Autodesk Fusion 360 part; units mm, degrees
(part 2 of 2)
sketch "草图103" plane through (0, 0, 0) normal (0, 0, 1) x (1, 0, 0) in component "scene_go"
  line L0 (9.75, 106.25) -> (32.75, 106.25) construction
  arc A0 (30.75, 106.25) -> (11.75, 106.25) centre (21.25, 87.3194) ccw
  arc A1 (11.75, 106.25) -> (30.75, 106.25) centre (21.25, 125.1806) ccw
revolve "旋转103" add sketch "草图103" angle 360 about axis through (9.75, 106.25, 0) along (1, 0, 0) separate body makes body 104 in component "scene_go"
sketch "草图104" plane through (0, 0, 0) normal (0, 0, 1) x (1, 0, 0) in component "scene_go"
  line L0 (9.75, 127.5) -> (32.75, 127.5) construction
  arc A0 (30.75, 127.5) -> (11.75, 127.5) centre (21.25, 108.5694) ccw
  arc A1 (11.75, 127.5) -> (30.75, 127.5) centre (21.25, 146.4306) ccw
revolve "旋转104" add sketch "草图104" angle 360 about axis through (9.75, 127.5, 0) along (1, 0, 0) separate body makes body 105 in component "scene_go"
sketch "草图105" plane through (0, 0, 0) normal (0, 0, 1) x (1, 0, 0) in component "scene_go"
  line L0 (31, -127.5) -> (54, -127.5) construction
  arc A0 (52, -127.5) -> (33, -127.5) centre (42.5, -146.4306) ccw
  arc A1 (33, -127.5) -> (52, -127.5) centre (42.5, -108.5694) ccw
revolve "旋转105" add sketch "草图105" angle 360 about axis through (31, -127.5, 0) along (1, 0, 0) separate body makes body 106 in component "scene_go"
sketch "草图106" plane through (0, 0, 0) normal (0, 0, 1) x (1, 0, 0) in component "scene_go"
  line L0 (31, -106.25) -> (54, -106.25) construction
  arc A0 (52, -106.25) -> (33, -106.25) centre (42.5, -125.1806) ccw
  arc A1 (33, -106.25) -> (52, -106.25) centre (42.5, -87.3194) ccw
revolve "旋转106" add sketch "草图106" angle 360 about axis through (31, -106.25, 0) along (1, 0, 0) separate body makes body 107 in component "scene_go"
sketch "草图107" plane through (0, 0, 0) normal (0, 0, 1) x (1, 0, 0) in component "scene_go"
  line L0 (31, -85) -> (54, -85) construction
  arc A0 (52, -85) -> (33, -85) centre (42.5, -103.9306) ccw
  arc A1 (33, -85) -> (52, -85) centre (42.5, -66.0694) ccw
revolve "旋转107" add sketch "草图107" angle 360 about axis through (31, -85, 0) along (1, 0, 0) separate body makes body 108 in component "scene_go"
sketch "草图108" plane through (0, 0, 0) normal (0, 0, 1) x (1, 0, 0) in component "scene_go"
  line L0 (31, -63.75) -> (54, -63.75) construction
  arc A0 (52, -63.75) -> (33, -63.75) centre (42.5, -82.6806) ccw
  arc A1 (33, -63.75) -> (52, -63.75) centre (42.5, -44.8194) ccw
revolve "旋转108" add sketch "草图108" angle 360 about axis through (31, -63.75, 0) along (1, 0, 0) separate body makes body 109 in component "scene_go"
sketch "草图109" plane through (0, 0, 0) normal (0, 0, 1) x (1, 0, 0) in component "scene_go"
  line L0 (31, -42.5) -> (54, -42.5) construction
  arc A0 (52, -42.5) -> (33, -42.5) centre (42.5, -61.4306) ccw
  arc A1 (33, -42.5) -> (52, -42.5) centre (42.5, -23.5694) ccw
revolve "旋转109" add sketch "草图109" angle 360 about axis through (31, -42.5, 0) along (1, 0, 0) separate body makes body 110 in component "scene_go"
sketch "草图110" plane through (0, 0, 0) normal (0, 0, 1) x (1, 0, 0) in component "scene_go"
  line L0 (31, -21.25) -> (54, -21.25) construction
  arc A0 (52, -21.25) -> (33, -21.25) centre (42.5, -40.1806) ccw
  arc A1 (33, -21.25) -> (52, -21.25) centre (42.5, -2.3194) ccw
revolve "旋转110" add sketch "草图110" angle 360 about axis through (31, -21.25, 0) along (1, 0, 0) separate body makes body 111 in component "scene_go"
sketch "草图111" plane through (0, 0, 0) normal (0, 0, 1) x (1, 0, 0) in component "scene_go"
  line L0 (31, 0) -> (54, 0) construction
  arc A0 (52, 0) -> (33, 0) centre (42.5, -18.9306) ccw
  arc A1 (33, 0) -> (52, 0) centre (42.5, 18.9306) ccw
revolve "旋转111" add sketch "草图111" angle 360 about axis through (31, 0, 0) along (1, 0, 0) separate body makes body 112 in component "scene_go"
sketch "草图112" plane through (0, 0, 0) normal (0, 0, 1) x (1, 0, 0) in component "scene_go"
  line L0 (31, 21.25) -> (54, 21.25) construction
  arc A0 (52, 21.25) -> (33, 21.25) centre (42.5, 2.3194) ccw
  arc A1 (33, 21.25) -> (52, 21.25) centre (42.5, 40.1806) ccw
revolve "旋转112" add sketch "草图112" angle 360 about axis through (31, 21.25, 0) along (1, 0, 0) separate body makes body 113 in component "scene_go"
sketch "草图113" plane through (0, 0, 0) normal (0, 0, 1) x (1, 0, 0) in component "scene_go"
  line L0 (31, 42.5) -> (54, 42.5) construction
  arc A0 (52, 42.5) -> (33, 42.5) centre (42.5, 23.5694) ccw
  arc A1 (33, 42.5) -> (52, 42.5) centre (42.5, 61.4306) ccw
revolve "旋转113" add sketch "草图113" angle 360 about axis through (31, 42.5, 0) along (1, 0, 0) separate body makes body 114 in component "scene_go"
sketch "草图114" plane through (0, 0, 0) normal (0, 0, 1) x (1, 0, 0) in component "scene_go"
  line L0 (31, 63.75) -> (54, 63.75) construction
  arc A0 (52, 63.75) -> (33, 63.75) centre (42.5, 44.8194) ccw
  arc A1 (33, 63.75) -> (52, 63.75) centre (42.5, 82.6806) ccw
revolve "旋转114" add sketch "草图114" angle 360 about axis through (31, 63.75, 0) along (1, 0, 0) separate body makes body 115 in component "scene_go"
sketch "草图115" plane through (0, 0, 0) normal (0, 0, 1) x (1, 0, 0) in component "scene_go"
  line L0 (31, 85) -> (54, 85) construction
  arc A0 (52, 85) -> (33, 85) centre (42.5, 66.0694) ccw
  arc A1 (33, 85) -> (52, 85) centre (42.5, 103.9306) ccw
revolve "旋转115" add sketch "草图115" angle 360 about axis through (31, 85, 0) along (1, 0, 0) separate body makes body 116 in component "scene_go"
sketch "草图116" plane through (0, 0, 0) normal (0, 0, 1) x (1, 0, 0) in component "scene_go"
  line L0 (31, 106.25) -> (54, 106.25) construction
  arc A0 (52, 106.25) -> (33, 106.25) centre (42.5, 87.3194) ccw
  arc A1 (33, 106.25) -> (52, 106.25) centre (42.5, 125.1806) ccw
revolve "旋转116" add sketch "草图116" angle 360 about axis through (31, 106.25, 0) along (1, 0, 0) separate body makes body 117 in component "scene_go"
sketch "草图117" plane through (0, 0, 0) normal (0, 0, 1) x (1, 0, 0) in component "scene_go"
  line L0 (31, 127.5) -> (54, 127.5) construction
  arc A0 (52, 127.5) -> (33, 127.5) centre (42.5, 108.5694) ccw
  arc A1 (33, 127.5) -> (52, 127.5) centre (42.5, 146.4306) ccw
revolve "旋转117" add sketch "草图117" angle 360 about axis through (31, 127.5, 0) along (1, 0, 0) separate body makes body 118 in component "scene_go"
sketch "草图118" plane through (0, 0, 0) normal (0, 0, 1) x (1, 0, 0) in component "scene_go"
  line L0 (52.25, -127.5) -> (75.25, -127.5) construction
  arc A0 (73.25, -127.5) -> (54.25, -127.5) centre (63.75, -146.4306) ccw
  arc A1 (54.25, -127.5) -> (73.25, -127.5) centre (63.75, -108.5694) ccw
revolve "旋转118" add sketch "草图118" angle 360 about axis through (52.25, -127.5, 0) along (1, 0, 0) separate body makes body 119 in component "scene_go"
sketch "草图119" plane through (0, 0, 0) normal (0, 0, 1) x (1, 0, 0) in component "scene_go"
  line L0 (52.25, -106.25) -> (75.25, -106.25) construction
  arc A0 (73.25, -106.25) -> (54.25, -106.25) centre (63.75, -125.1806) ccw
  arc A1 (54.25, -106.25) -> (73.25, -106.25) centre (63.75, -87.3194) ccw
revolve "旋转119" add sketch "草图119" angle 360 about axis through (52.25, -106.25, 0) along (1, 0, 0) separate body makes body 120 in component "scene_go"
sketch "草图120" plane through (0, 0, 0) normal (0, 0, 1) x (1, 0, 0) in component "scene_go"
  line L0 (52.25, -85) -> (75.25, -85) construction
  arc A0 (73.25, -85) -> (54.25, -85) centre (63.75, -103.9306) ccw
  arc A1 (54.25, -85) -> (73.25, -85) centre (63.75, -66.0694) ccw
revolve "旋转120" add sketch "草图120" angle 360 about axis through (52.25, -85, 0) along (1, 0, 0) separate body makes body 121 in component "scene_go"
sketch "草图121" plane through (0, 0, 0) normal (0, 0, 1) x (1, 0, 0) in component "scene_go"
  line L0 (52.25, -63.75) -> (75.25, -63.75) construction
  arc A0 (73.25, -63.75) -> (54.25, -63.75) centre (63.75, -82.6806) ccw
  arc A1 (54.25, -63.75) -> (73.25, -63.75) centre (63.75, -44.8194) ccw
revolve "旋转121" add sketch "草图121" angle 360 about axis through (52.25, -63.75, 0) along (1, 0, 0) separate body makes body 122 in component "scene_go"
sketch "草图122" plane through (0, 0, 0) normal (0, 0, 1) x (1, 0, 0) in component "scene_go"
  line L0 (52.25, -42.5) -> (75.25, -42.5) construction
  arc A0 (73.25, -42.5) -> (54.25, -42.5) centre (63.75, -61.4306) ccw
  arc A1 (54.25, -42.5) -> (73.25, -42.5) centre (63.75, -23.5694) ccw
revolve "旋转122" add sketch "草图122" angle 360 about axis through (52.25, -42.5, 0) along (1, 0, 0) separate body makes body 123 in component "scene_go"
sketch "草图123" plane through (0, 0, 0) normal (0, 0, 1) x (1, 0, 0) in component "scene_go"
  line L0 (52.25, -21.25) -> (75.25, -21.25) construction
  arc A0 (73.25, -21.25) -> (54.25, -21.25) centre (63.75, -40.1806) ccw
  arc A1 (54.25, -21.25) -> (73.25, -21.25) centre (63.75, -2.3194) ccw
revolve "旋转123" add sketch "草图123" angle 360 about axis through (52.25, -21.25, 0) along (1, 0, 0) separate body makes body 124 in component "scene_go"
sketch "草图124" plane through (0, 0, 0) normal (0, 0, 1) x (1, 0, 0) in component "scene_go"
  line L0 (52.25, 0) -> (75.25, 0) construction
  arc A0 (73.25, 0) -> (54.25, 0) centre (63.75, -18.9306) ccw
  arc A1 (54.25, 0) -> (73.25, 0) centre (63.75, 18.9306) ccw
revolve "旋转124" add sketch "草图124" angle 360 about axis through (52.25, 0, 0) along (1, 0, 0) separate body makes body 125 in component "scene_go"
sketch "草图125" plane through (0, 0, 0) normal (0, 0, 1) x (1, 0, 0) in component "scene_go"
  line L0 (52.25, 21.25) -> (75.25, 21.25) construction
  arc A0 (73.25, 21.25) -> (54.25, 21.25) centre (63.75, 2.3194) ccw
  arc A1 (54.25, 21.25) -> (73.25, 21.25) centre (63.75, 40.1806) ccw
revolve "旋转125" add sketch "草图125" angle 360 about axis through (52.25, 21.25, 0) along (1, 0, 0) separate body makes body 126 in component "scene_go"
sketch "草图126" plane through (0, 0, 0) normal (0, 0, 1) x (1, 0, 0) in component "scene_go"
  line L0 (52.25, 42.5) -> (75.25, 42.5) construction
  arc A0 (73.25, 42.5) -> (54.25, 42.5) centre (63.75, 23.5694) ccw
  arc A1 (54.25, 42.5) -> (73.25, 42.5) centre (63.75, 61.4306) ccw
revolve "旋转126" add sketch "草图126" angle 360 about axis through (52.25, 42.5, 0) along (1, 0, 0) separate body makes body 127 in component "scene_go"
sketch "草图127" plane through (0, 0, 0) normal (0, 0, 1) x (1, 0, 0) in component "scene_go"
  line L0 (52.25, 63.75) -> (75.25, 63.75) construction
  arc A0 (73.25, 63.75) -> (54.25, 63.75) centre (63.75, 44.8194) ccw
  arc A1 (54.25, 63.75) -> (73.25, 63.75) centre (63.75, 82.6806) ccw
revolve "旋转127" add sketch "草图127" angle 360 about axis through (52.25, 63.75, 0) along (1, 0, 0) separate body makes body 128 in component "scene_go"
sketch "草图128" plane through (0, 0, 0) normal (0, 0, 1) x (1, 0, 0) in component "scene_go"
  line L0 (52.25, 85) -> (75.25, 85) construction
  arc A0 (73.25, 85) -> (54.25, 85) centre (63.75, 66.0694) ccw
  arc A1 (54.25, 85) -> (73.25, 85) centre (63.75, 103.9306) ccw
revolve "旋转128" add sketch "草图128" angle 360 about axis through (52.25, 85, 0) along (1, 0, 0) separate body makes body 129 in component "scene_go"
sketch "草图129" plane through (0, 0, 0) normal (0, 0, 1) x (1, 0, 0) in component "scene_go"
  line L0 (52.25, 106.25) -> (75.25, 106.25) construction
  arc A0 (73.25, 106.25) -> (54.25, 106.25) centre (63.75, 87.3194) ccw
  arc A1 (54.25, 106.25) -> (73.25, 106.25) centre (63.75, 125.1806) ccw
revolve "旋转129" add sketch "草图129" angle 360 about axis through (52.25, 106.25, 0) along (1, 0, 0) separate body makes body 130 in component "scene_go"
sketch "草图130" plane through (0, 0, 0) normal (0, 0, 1) x (1, 0, 0) in component "scene_go"
  line L0 (52.25, 127.5) -> (75.25, 127.5) construction
  arc A0 (73.25, 127.5) -> (54.25, 127.5) centre (63.75, 108.5694) ccw
  arc A1 (54.25, 127.5) -> (73.25, 127.5) centre (63.75, 146.4306) ccw
revolve "旋转130" add sketch "草图130" angle 360 about axis through (52.25, 127.5, 0) along (1, 0, 0) separate body makes body 131 in component "scene_go"
sketch "草图131" plane through (0, 0, 0) normal (0, 0, 1) x (1, 0, 0) in component "scene_go"
  line L0 (73.5, -127.5) -> (96.5, -127.5) construction
  arc A0 (94.5, -127.5) -> (75.5, -127.5) centre (85, -146.4306) ccw
  arc A1 (75.5, -127.5) -> (94.5, -127.5) centre (85, -108.5694) ccw
revolve "旋转131" add sketch "草图131" angle 360 about axis through (73.5, -127.5, 0) along (1, 0, 0) separate body makes body 132 in component "scene_go"
sketch "草图132" plane through (0, 0, 0) normal (0, 0, 1) x (1, 0, 0) in component "scene_go"
  line L0 (73.5, -106.25) -> (96.5, -106.25) construction
  arc A0 (94.5, -106.25) -> (75.5, -106.25) centre (85, -125.1806) ccw
  arc A1 (75.5, -106.25) -> (94.5, -106.25) centre (85, -87.3194) ccw
revolve "旋转132" add sketch "草图132" angle 360 about axis through (73.5, -106.25, 0) along (1, 0, 0) separate body makes body 133 in component "scene_go"
sketch "草图133" plane through (0, 0, 0) normal (0, 0, 1) x (1, 0, 0) in component "scene_go"
  line L0 (73.5, -85) -> (96.5, -85) construction
  arc A0 (94.5, -85) -> (75.5, -85) centre (85, -103.9306) ccw
  arc A1 (75.5, -85) -> (94.5, -85) centre (85, -66.0694) ccw
revolve "旋转133" add sketch "草图133" angle 360 about axis through (73.5, -85, 0) along (1, 0, 0) separate body makes body 134 in component "scene_go"
sketch "草图134" plane through (0, 0, 0) normal (0, 0, 1) x (1, 0, 0) in component "scene_go"
  line L0 (73.5, -63.75) -> (96.5, -63.75) construction
  arc A0 (94.5, -63.75) -> (75.5, -63.75) centre (85, -82.6806) ccw
  arc A1 (75.5, -63.75) -> (94.5, -63.75) centre (85, -44.8194) ccw
revolve "旋转134" add sketch "草图134" angle 360 about axis through (73.5, -63.75, 0) along (1, 0, 0) separate body makes body 135 in component "scene_go"
sketch "草图135" plane through (0, 0, 0) normal (0, 0, 1) x (1, 0, 0) in component "scene_go"
  line L0 (73.5, -42.5) -> (96.5, -42.5) construction
  arc A0 (94.5, -42.5) -> (75.5, -42.5) centre (85, -61.4306) ccw
  arc A1 (75.5, -42.5) -> (94.5, -42.5) centre (85, -23.5694) ccw
revolve "旋转135" add sketch "草图135" angle 360 about axis through (73.5, -42.5, 0) along (1, 0, 0) separate body makes body 136 in component "scene_go"
sketch "草图136" plane through (0, 0, 0) normal (0, 0, 1) x (1, 0, 0) in component "scene_go"
  line L0 (73.5, -21.25) -> (96.5, -21.25) construction
  arc A0 (94.5, -21.25) -> (75.5, -21.25) centre (85, -40.1806) ccw
  arc A1 (75.5, -21.25) -> (94.5, -21.25) centre (85, -2.3194) ccw
revolve "旋转136" add sketch "草图136" angle 360 about axis through (73.5, -21.25, 0) along (1, 0, 0) separate body makes body 137 in component "scene_go"
sketch "草图137" plane through (0, 0, 0) normal (0, 0, 1) x (1, 0, 0) in component "scene_go"
  line L0 (73.5, 0) -> (96.5, 0) construction
  arc A0 (94.5, 0) -> (75.5, 0) centre (85, -18.9306) ccw
  arc A1 (75.5, 0) -> (94.5, 0) centre (85, 18.9306) ccw
revolve "旋转137" add sketch "草图137" angle 360 about axis through (73.5, 0, 0) along (1, 0, 0) separate body makes body 138 in component "scene_go"
sketch "草图138" plane through (0, 0, 0) normal (0, 0, 1) x (1, 0, 0) in component "scene_go"
  line L0 (73.5, 21.25) -> (96.5, 21.25) construction
  arc A0 (94.5, 21.25) -> (75.5, 21.25) centre (85, 2.3194) ccw
  arc A1 (75.5, 21.25) -> (94.5, 21.25) centre (85, 40.1806) ccw
revolve "旋转138" add sketch "草图138" angle 360 about axis through (73.5, 21.25, 0) along (1, 0, 0) separate body makes body 139 in component "scene_go"
sketch "草图139" plane through (0, 0, 0) normal (0, 0, 1) x (1, 0, 0) in component "scene_go"
  line L0 (73.5, 42.5) -> (96.5, 42.5) construction
  arc A0 (94.5, 42.5) -> (75.5, 42.5) centre (85, 23.5694) ccw
  arc A1 (75.5, 42.5) -> (94.5, 42.5) centre (85, 61.4306) ccw
revolve "旋转139" add sketch "草图139" angle 360 about axis through (73.5, 42.5, 0) along (1, 0, 0) separate body makes body 140 in component "scene_go"
sketch "草图140" plane through (0, 0, 0) normal (0, 0, 1) x (1, 0, 0) in component "scene_go"
  line L0 (73.5, 63.75) -> (96.5, 63.75) construction
  arc A0 (94.5, 63.75) -> (75.5, 63.75) centre (85, 44.8194) ccw
  arc A1 (75.5, 63.75) -> (94.5, 63.75) centre (85, 82.6806) ccw
revolve "旋转140" add sketch "草图140" angle 360 about axis through (73.5, 63.75, 0) along (1, 0, 0) separate body makes body 141 in component "scene_go"
sketch "草图141" plane through (0, 0, 0) normal (0, 0, 1) x (1, 0, 0) in component "scene_go"
  line L0 (73.5, 85) -> (96.5, 85) construction
  arc A0 (94.5, 85) -> (75.5, 85) centre (85, 66.0694) ccw
  arc A1 (75.5, 85) -> (94.5, 85) centre (85, 103.9306) ccw
revolve "旋转141" add sketch "草图141" angle 360 about axis through (73.5, 85, 0) along (1, 0, 0) separate body makes body 142 in component "scene_go"
sketch "草图142" plane through (0, 0, 0) normal (0, 0, 1) x (1, 0, 0) in component "scene_go"
  line L0 (73.5, 106.25) -> (96.5, 106.25) construction
  arc A0 (94.5, 106.25) -> (75.5, 106.25) centre (85, 87.3194) ccw
  arc A1 (75.5, 106.25) -> (94.5, 106.25) centre (85, 125.1806) ccw
revolve "旋转142" add sketch "草图142" angle 360 about axis through (73.5, 106.25, 0) along (1, 0, 0) separate body makes body 143 in component "scene_go"
sketch "草图143" plane through (0, 0, 0) normal (0, 0, 1) x (1, 0, 0) in component "scene_go"
  line L0 (73.5, 127.5) -> (96.5, 127.5) construction
  arc A0 (94.5, 127.5) -> (75.5, 127.5) centre (85, 108.5694) ccw
  arc A1 (75.5, 127.5) -> (94.5, 127.5) centre (85, 146.4306) ccw
revolve "旋转143" add sketch "草图143" angle 360 about axis through (73.5, 127.5, 0) along (1, 0, 0) separate body makes body 144 in component "scene_go"
sketch "草图144" plane through (0, 0, 0) normal (0, 0, 1) x (1, 0, 0) in component "scene_go"
  line L0 (94.75, -127.5) -> (117.75, -127.5) construction
  arc A0 (115.75, -127.5) -> (96.75, -127.5) centre (106.25, -146.4306) ccw
  arc A1 (96.75, -127.5) -> (115.75, -127.5) centre (106.25, -108.5694) ccw
revolve "旋转144" add sketch "草图144" angle 360 about axis through (94.75, -127.5, 0) along (1, 0, 0) separate body makes body 145 in component "scene_go"
sketch "草图145" plane through (0, 0, 0) normal (0, 0, 1) x (1, 0, 0) in component "scene_go"
  line L0 (94.75, -106.25) -> (117.75, -106.25) construction
  arc A0 (115.75, -106.25) -> (96.75, -106.25) centre (106.25, -125.1806) ccw
  arc A1 (96.75, -106.25) -> (115.75, -106.25) centre (106.25, -87.3194) ccw
revolve "旋转145" add sketch "草图145" angle 360 about axis through (94.75, -106.25, 0) along (1, 0, 0) separate body makes body 146 in component "scene_go"
sketch "草图146" plane through (0, 0, 0) normal (0, 0, 1) x (1, 0, 0) in component "scene_go"
  line L0 (94.75, -85) -> (117.75, -85) construction
  arc A0 (115.75, -85) -> (96.75, -85) centre (106.25, -103.9306) ccw
  arc A1 (96.75, -85) -> (115.75, -85) centre (106.25, -66.0694) ccw
revolve "旋转146" add sketch "草图146" angle 360 about axis through (94.75, -85, 0) along (1, 0, 0) separate body makes body 147 in component "scene_go"
sketch "草图147" plane through (0, 0, 0) normal (0, 0, 1) x (1, 0, 0) in component "scene_go"
  line L0 (94.75, -63.75) -> (117.75, -63.75) construction
  arc A0 (115.75, -63.75) -> (96.75, -63.75) centre (106.25, -82.6806) ccw
  arc A1 (96.75, -63.75) -> (115.75, -63.75) centre (106.25, -44.8194) ccw
revolve "旋转147" add sketch "草图147" angle 360 about axis through (94.75, -63.75, 0) along (1, 0, 0) separate body makes body 148 in component "scene_go"
sketch "草图148" plane through (0, 0, 0) normal (0, 0, 1) x (1, 0, 0) in component "scene_go"
  line L0 (94.75, -42.5) -> (117.75, -42.5) construction
  arc A0 (115.75, -42.5) -> (96.75, -42.5) centre (106.25, -61.4306) ccw
  arc A1 (96.75, -42.5) -> (115.75, -42.5) centre (106.25, -23.5694) ccw
revolve "旋转148" add sketch "草图148" angle 360 about axis through (94.75, -42.5, 0) along (1, 0, 0) separate body makes body 149 in component "scene_go"
sketch "草图149" plane through (0, 0, 0) normal (0, 0, 1) x (1, 0, 0) in component "scene_go"
  line L0 (94.75, -21.25) -> (117.75, -21.25) construction
  arc A0 (115.75, -21.25) -> (96.75, -21.25) centre (106.25, -40.1806) ccw
  arc A1 (96.75, -21.25) -> (115.75, -21.25) centre (106.25, -2.3194) ccw
revolve "旋转149" add sketch "草图149" angle 360 about axis through (94.75, -21.25, 0) along (1, 0, 0) separate body makes body 150 in component "scene_go"
sketch "草图150" plane through (0, 0, 0) normal (0, 0, 1) x (1, 0, 0) in component "scene_go"
  line L0 (94.75, 0) -> (117.75, 0) construction
  arc A0 (115.75, 0) -> (96.75, 0) centre (106.25, -18.9306) ccw
  arc A1 (96.75, 0) -> (115.75, 0) centre (106.25, 18.9306) ccw
revolve "旋转150" add sketch "草图150" angle 360 about axis through (94.75, 0, 0) along (1, 0, 0) separate body makes body 151 in component "scene_go"
sketch "草图151" plane through (0, 0, 0) normal (0, 0, 1) x (1, 0, 0) in component "scene_go"
  line L0 (94.75, 21.25) -> (117.75, 21.25) construction
  arc A0 (115.75, 21.25) -> (96.75, 21.25) centre (106.25, 2.3194) ccw
  arc A1 (96.75, 21.25) -> (115.75, 21.25) centre (106.25, 40.1806) ccw
revolve "旋转151" add sketch "草图151" angle 360 about axis through (94.75, 21.25, 0) along (1, 0, 0) separate body makes body 152 in component "scene_go"
sketch "草图152" plane through (0, 0, 0) normal (0, 0, 1) x (1, 0, 0) in component "scene_go"
  line L0 (94.75, 42.5) -> (117.75, 42.5) construction
  arc A0 (115.75, 42.5) -> (96.75, 42.5) centre (106.25, 23.5694) ccw
  arc A1 (96.75, 42.5) -> (115.75, 42.5) centre (106.25, 61.4306) ccw
revolve "旋转152" add sketch "草图152" angle 360 about axis through (94.75, 42.5, 0) along (1, 0, 0) separate body makes body 153 in component "scene_go"
sketch "草图153" plane through (0, 0, 0) normal (0, 0, 1) x (1, 0, 0) in component "scene_go"
  line L0 (94.75, 63.75) -> (117.75, 63.75) construction
  arc A0 (115.75, 63.75) -> (96.75, 63.75) centre (106.25, 44.8194) ccw
  arc A1 (96.75, 63.75) -> (115.75, 63.75) centre (106.25, 82.6806) ccw
revolve "旋转153" add sketch "草图153" angle 360 about axis through (94.75, 63.75, 0) along (1, 0, 0) separate body makes body 154 in component "scene_go"
sketch "草图154" plane through (0, 0, 0) normal (0, 0, 1) x (1, 0, 0) in component "scene_go"
  line L0 (94.75, 85) -> (117.75, 85) construction
  arc A0 (115.75, 85) -> (96.75, 85) centre (106.25, 66.0694) ccw
  arc A1 (96.75, 85) -> (115.75, 85) centre (106.25, 103.9306) ccw
revolve "旋转154" add sketch "草图154" angle 360 about axis through (94.75, 85, 0) along (1, 0, 0) separate body makes body 155 in component "scene_go"
sketch "草图155" plane through (0, 0, 0) normal (0, 0, 1) x (1, 0, 0) in component "scene_go"
  line L0 (94.75, 106.25) -> (117.75, 106.25) construction
  arc A0 (115.75, 106.25) -> (96.75, 106.25) centre (106.25, 87.3194) ccw
  arc A1 (96.75, 106.25) -> (115.75, 106.25) centre (106.25, 125.1806) ccw
revolve "旋转155" add sketch "草图155" angle 360 about axis through (94.75, 106.25, 0) along (1, 0, 0) separate body makes body 156 in component "scene_go"
sketch "草图156" plane through (0, 0, 0) normal (0, 0, 1) x (1, 0, 0) in component "scene_go"
  line L0 (94.75, 127.5) -> (117.75, 127.5) construction
  arc A0 (115.75, 127.5) -> (96.75, 127.5) centre (106.25, 108.5694) ccw
  arc A1 (96.75, 127.5) -> (115.75, 127.5) centre (106.25, 146.4306) ccw
revolve "旋转156" add sketch "草图156" angle 360 about axis through (94.75, 127.5, 0) along (1, 0, 0) separate body makes body 157 in component "scene_go"
sketch "草图157" plane through (0, 0, 0) normal (0, 0, 1) x (1, 0, 0) in component "scene_go"
  line L0 (116, -127.5) -> (139, -127.5) construction
  arc A0 (137, -127.5) -> (118, -127.5) centre (127.5, -146.4306) ccw
  arc A1 (118, -127.5) -> (137, -127.5) centre (127.5, -108.5694) ccw
revolve "旋转157" add sketch "草图157" angle 360 about axis through (116, -127.5, 0) along (1, 0, 0) separate body makes body 158 in component "scene_go"
sketch "草图158" plane through (0, 0, 0) normal (0, 0, 1) x (1, 0, 0) in component "scene_go"
  line L0 (116, -106.25) -> (139, -106.25) construction
  arc A0 (137, -106.25) -> (118, -106.25) centre (127.5, -125.1806) ccw
  arc A1 (118, -106.25) -> (137, -106.25) centre (127.5, -87.3194) ccw
revolve "旋转158" add sketch "草图158" angle 360 about axis through (116, -106.25, 0) along (1, 0, 0) separate body makes body 159 in component "scene_go"
sketch "草图159" plane through (0, 0, 0) normal (0, 0, 1) x (1, 0, 0) in component "scene_go"
  line L0 (116, -85) -> (139, -85) construction
  arc A0 (137, -85) -> (118, -85) centre (127.5, -103.9306) ccw
  arc A1 (118, -85) -> (137, -85) centre (127.5, -66.0694) ccw
revolve "旋转159" add sketch "草图159" angle 360 about axis through (116, -85, 0) along (1, 0, 0) separate body makes body 160 in component "scene_go"
sketch "草图160" plane through (0, 0, 0) normal (0, 0, 1) x (1, 0, 0) in component "scene_go"
  line L0 (116, -63.75) -> (139, -63.75) construction
  arc A0 (137, -63.75) -> (118, -63.75) centre (127.5, -82.6806) ccw
  arc A1 (118, -63.75) -> (137, -63.75) centre (127.5, -44.8194) ccw
revolve "旋转160" add sketch "草图160" angle 360 about axis through (116, -63.75, 0) along (1, 0, 0) separate body makes body 161 in component "scene_go"
sketch "草图161" plane through (0, 0, 0) normal (0, 0, 1) x (1, 0, 0) in component "scene_go"
  line L0 (116, -42.5) -> (139, -42.5) construction
  arc A0 (137, -42.5) -> (118, -42.5) centre (127.5, -61.4306) ccw
  arc A1 (118, -42.5) -> (137, -42.5) centre (127.5, -23.5694) ccw
revolve "旋转161" add sketch "草图161" angle 360 about axis through (116, -42.5, 0) along (1, 0, 0) separate body makes body 162 in component "scene_go"
sketch "草图162" plane through (0, 0, 0) normal (0, 0, 1) x (1, 0, 0) in component "scene_go"
  line L0 (116, -21.25) -> (139, -21.25) construction
  arc A0 (137, -21.25) -> (118, -21.25) centre (127.5, -40.1806) ccw
  arc A1 (118, -21.25) -> (137, -21.25) centre (127.5, -2.3194) ccw
revolve "旋转162" add sketch "草图162" angle 360 about axis through (116, -21.25, 0) along (1, 0, 0) separate body makes body 163 in component "scene_go"
sketch "草图163" plane through (0, 0, 0) normal (0, 0, 1) x (1, 0, 0) in component "scene_go"
  line L0 (116, 0) -> (139, 0) construction
  arc A0 (137, 0) -> (118, 0) centre (127.5, -18.9306) ccw
  arc A1 (118, 0) -> (137, 0) centre (127.5, 18.9306) ccw
revolve "旋转163" add sketch "草图163" angle 360 about axis through (116, 0, 0) along (1, 0, 0) separate body makes body 164 in component "scene_go"
sketch "草图164" plane through (0, 0, 0) normal (0, 0, 1) x (1, 0, 0) in component "scene_go"
  line L0 (116, 21.25) -> (139, 21.25) construction
  arc A0 (137, 21.25) -> (118, 21.25) centre (127.5, 2.3194) ccw
  arc A1 (118, 21.25) -> (137, 21.25) centre (127.5, 40.1806) ccw
revolve "旋转164" add sketch "草图164" angle 360 about axis through (116, 21.25, 0) along (1, 0, 0) separate body makes body 165 in component "scene_go"
sketch "草图165" plane through (0, 0, 0) normal (0, 0, 1) x (1, 0, 0) in component "scene_go"
  line L0 (116, 42.5) -> (139, 42.5) construction
  arc A0 (137, 42.5) -> (118, 42.5) centre (127.5, 23.5694) ccw
  arc A1 (118, 42.5) -> (137, 42.5) centre (127.5, 61.4306) ccw
revolve "旋转165" add sketch "草图165" angle 360 about axis through (116, 42.5, 0) along (1, 0, 0) separate body makes body 166 in component "scene_go"
sketch "草图166" plane through (0, 0, 0) normal (0, 0, 1) x (1, 0, 0) in component "scene_go"
  line L0 (116, 63.75) -> (139, 63.75) construction
  arc A0 (137, 63.75) -> (118, 63.75) centre (127.5, 44.8194) ccw
  arc A1 (118, 63.75) -> (137, 63.75) centre (127.5, 82.6806) ccw
revolve "旋转166" add sketch "草图166" angle 360 about axis through (116, 63.75, 0) along (1, 0, 0) separate body makes body 167 in component "scene_go"
sketch "草图167" plane through (0, 0, 0) normal (0, 0, 1) x (1, 0, 0) in component "scene_go"
  line L0 (116, 85) -> (139, 85) construction
  arc A0 (137, 85) -> (118, 85) centre (127.5, 66.0694) ccw
  arc A1 (118, 85) -> (137, 85) centre (127.5, 103.9306) ccw
revolve "旋转167" add sketch "草图167" angle 360 about axis through (116, 85, 0) along (1, 0, 0) separate body makes body 168 in component "scene_go"
sketch "草图168" plane through (0, 0, 0) normal (0, 0, 1) x (1, 0, 0) in component "scene_go"
  line L0 (116, 106.25) -> (139, 106.25) construction
  arc A0 (137, 106.25) -> (118, 106.25) centre (127.5, 87.3194) ccw
  arc A1 (118, 106.25) -> (137, 106.25) centre (127.5, 125.1806) ccw
revolve "旋转168" add sketch "草图168" angle 360 about axis through (116, 106.25, 0) along (1, 0, 0) separate body makes body 169 in component "scene_go"
sketch "草图169" plane through (0, 0, 0) normal (0, 0, 1) x (1, 0, 0) in component "scene_go"
  line L0 (116, 127.5) -> (139, 127.5) construction
  arc A0 (137, 127.5) -> (118, 127.5) centre (127.5, 108.5694) ccw
  arc A1 (118, 127.5) -> (137, 127.5) centre (127.5, 146.4306) ccw
revolve "旋转169" add sketch "草图169" angle 360 about axis through (116, 127.5, 0) along (1, 0, 0) separate body makes body 170 in component "scene_go"
component "scene_board" placed x (1, 0, 0) y (0, 1, 0) z (0, 0, 1) at (0, 0, 0)
component "scene_go" placed x (1, 0, 0) y (0, 1, 0) z (0, 0, 1) at (0, 0, 0)
